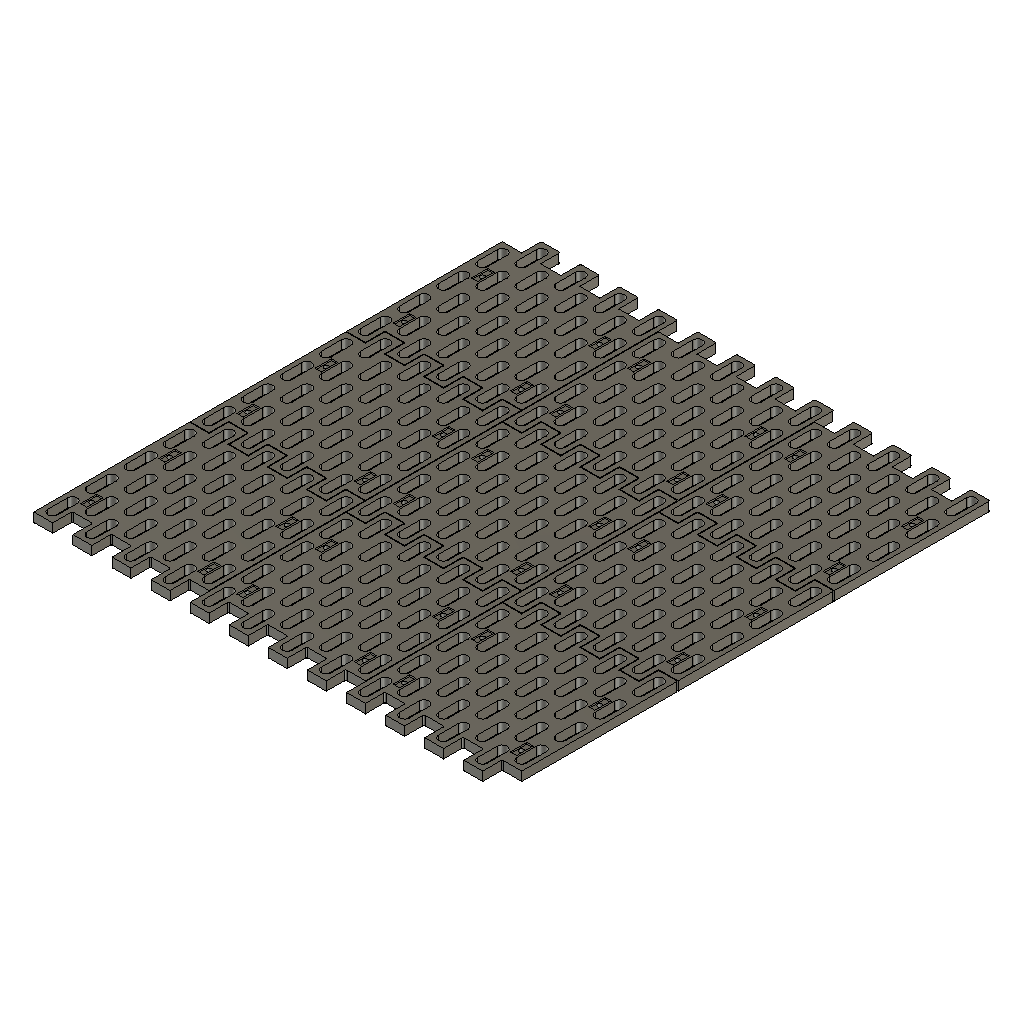
seam-array-3x3-gap-0.35 (Autodesk Fusion 360 design; units mm, degrees)
part number: 2026-10-31-10-06-00-765
part number: 2026-10-31-10-06-01-089
Autodesk Fusion 360 part; units mm, degrees
sketch "01 Main panel web sketch" plane through (0, 0, 0) normal (0, 0, 1) x (1, 0, 0) in component "Panel 80 mm whole-slot coupon"
  line L0 (0.175, 0.175) -> (79.825, 0.175)
  line L1 (79.825, 0.175) -> (79.825, 79.825)
  line L2 (79.825, 79.825) -> (0.175, 79.825)
  line L3 (0.175, 79.825) -> (0.175, 0.175)
  dimension "d71" = 0.175
  dimension "d72" = 0.175
  dimension "d73" = 79.65
  dimension "d74" = 79.65
  constraint horizontal L0
  constraint vertical L1
  constraint horizontal L2
  constraint vertical L3
  measures "d71" horizontal distance of origin L0.start
  measures "d72" vertical distance of origin L0.start
  measures "d73" horizontal distance of L0.start L0.end
  measures "d74" vertical distance of L0.end L1.end
extrude "01 Main panel web" add sketch "01 Main panel web sketch" along normal blind 5 in component "Panel 80 mm whole-slot coupon"
sketch "02 Whole-slot upper tooth sketch" plane through (0, 0, 0) normal (0, 0, 1) x (1, 0, 0) in component "Panel 80 mm whole-slot coupon"
  line L0 (10.175, 79) -> (19.825, 79)
  line L1 (19.825, 79) -> (19.825, 89.825)
  line L2 (19.825, 89.825) -> (10.175, 89.825)
  line L3 (10.175, 89.825) -> (10.175, 79)
  dimension "d77" = 10.175
  dimension "d78" = 79
  dimension "d79" = 9.65
  dimension "d80" = 10.825
  constraint horizontal L0
  constraint vertical L1
  constraint horizontal L2
  constraint vertical L3
  measures "d77" horizontal distance of origin L0.start
  measures "d78" vertical distance of origin L0.start
  measures "d79" horizontal distance of L0.start L0.end
  measures "d80" vertical distance of L0.end L1.end
extrude "02 Whole-slot upper tooth" add sketch "02 Whole-slot upper tooth sketch" along normal blind 5 in component "Panel 80 mm whole-slot coupon"
fillet "02 Rounded tooth tip seed" radius 0.6 2 edges at (19.825, 89.825, 2.5) (10.175, 89.825, 2.5) in component "Panel 80 mm whole-slot coupon"
pattern_linear "03 Upper teeth and rounding follow column count" count 4 spacing 20 along (1, 0, 0) of "02 Whole-slot upper tooth", "02 Rounded tooth tip seed" in component "Panel 80 mm whole-slot coupon"
sketch "04 Lower receiving step sketch" plane through (0, 0, 0) normal (0, 0, 1) x (1, 0, 0) in component "Panel 80 mm whole-slot coupon"
  line L0 (9.825, -1) -> (20.175, -1)
  line L1 (20.175, -1) -> (20.175, 10.175)
  line L2 (20.175, 10.175) -> (9.825, 10.175)
  line L3 (9.825, 10.175) -> (9.825, -1)
  dimension "d89" = 9.825
  dimension "d90" = 1
  dimension "d91" = 10.35
  dimension "d92" = 11.175
  constraint horizontal L0
  constraint vertical L1
  constraint horizontal L2
  constraint vertical L3
  measures "d89" horizontal distance of origin L0.start
  measures "d90" vertical distance of origin L0.start
  measures "d91" horizontal distance of L0.start L0.end
  measures "d92" vertical distance of L0.end L1.end
extrude "04 Lower receiving step" cut sketch "04 Lower receiving step sketch" along normal blind 5 in component "Panel 80 mm whole-slot coupon"
fillet "04 Rounded receiving step seed" radius 0.6 2 edges at (20.175, 10.175, 2.5) (9.825, 10.175, 2.5) in component "Panel 80 mm whole-slot coupon"
pattern_linear "05 Receiving steps and rounding follow column count" count 3 spacing 20 along (1, 0, 0) of "04 Lower receiving step", "04 Rounded receiving step seed" in component "Panel 80 mm whole-slot coupon"
sketch "05 Terminal receiving step sketch" plane through (0, 0, 0) normal (0, 0, 1) x (1, 0, 0) in component "Panel 80 mm whole-slot coupon"
  line L0 (69.825, -1) -> (80.175, -1)
  line L1 (80.175, -1) -> (80.175, 10.175)
  line L2 (80.175, 10.175) -> (69.825, 10.175)
  line L3 (69.825, 10.175) -> (69.825, -1)
  dimension "d101" = 69.825
  dimension "d102" = 1
  dimension "d103" = 10.35
  dimension "d104" = 11.175
  constraint horizontal L0
  constraint vertical L1
  constraint horizontal L2
  constraint vertical L3
  measures "d101" horizontal distance of origin L0.start
  measures "d102" vertical distance of origin L0.start
  measures "d103" horizontal distance of L0.start L0.end
  measures "d104" vertical distance of L0.end L1.end
extrude "05 Terminal receiving step" cut sketch "05 Terminal receiving step sketch" along normal blind 5 in component "Panel 80 mm whole-slot coupon"
fillet "05 Rounded terminal receiving step" radius 0.6 1 edges at (69.825, 10.175, 2.5) in component "Panel 80 mm whole-slot coupon"
sketch "08 Whole A slots constrained seed" plane through (0, 0, 0) normal (0, 0, 1) x (1, 0, 0) in component "Panel 80 mm whole-slot coupon"
  line L0 (7.5, 5) -> (7.5, 15)
  arc A0 (7.5, 15) -> (2.5, 15) centre (5, 15) ccw
  line L1 (2.5, 15) -> (2.5, 5)
  arc A1 (2.5, 5) -> (7.5, 5) centre (5, 5) ccw
  line L2 (5, 5) -> (5, 15) construction
  line L3 (5, 5) -> (15, 5) construction
  dimension "d109" = 5
  dimension "d110" = 10
  dimension "d111" = 90
  dimension "d112" = 10
  dimension "d113" = 5
  dimension "d114" = 5
  constraint tangent L0 A0
  constraint tangent A0 L1
  constraint tangent L1 A1
  constraint tangent L0 A1
  constraint parallel L0 L1
  constraint horizontal L3
  measures "d109" diameter of A0
  measures "d110" distance of A1.centre A0.centre
  measures "d111" angle of L2 L3
  measures "d112" horizontal distance of A1.centre L3.end
  measures "d113" horizontal distance of origin A1.centre
  measures "d114" vertical distance of origin A1.centre
extrude "08 Whole A slots through cut" cut sketch "08 Whole A slots constrained seed" along normal blind 5 in component "Panel 80 mm whole-slot coupon"
pattern_linear "08 Whole A slots lattice" count 4 spacing 20 along (1, 0, 0) count 4 spacing 20 along (0, 1, 0) of "08 Whole A slots through cut" in component "Panel 80 mm whole-slot coupon"
sketch "09 Whole B slots owned by this panel constrained seed" plane through (0, 0, 0) normal (0, 0, 1) x (1, 0, 0) in component "Panel 80 mm whole-slot coupon"
  line L0 (17.5, 15) -> (17.5, 25)
  arc A0 (17.5, 25) -> (12.5, 25) centre (15, 25) ccw
  line L1 (12.5, 25) -> (12.5, 15)
  arc A1 (12.5, 15) -> (17.5, 15) centre (15, 15) ccw
  line L2 (15, 15) -> (15, 25) construction
  line L3 (15, 15) -> (25, 15) construction
  dimension "d121" = 5
  dimension "d122" = 10
  dimension "d123" = 90
  dimension "d124" = 10
  dimension "d125" = 15
  dimension "d126" = 15
  constraint tangent L0 A0
  constraint tangent A0 L1
  constraint tangent L1 A1
  constraint tangent L0 A1
  constraint parallel L0 L1
  constraint horizontal L3
  measures "d121" diameter of A0
  measures "d122" distance of A1.centre A0.centre
  measures "d123" angle of L2 L3
  measures "d124" horizontal distance of A1.centre L3.end
  measures "d125" horizontal distance of origin A1.centre
  measures "d126" vertical distance of origin A1.centre
extrude "09 Whole B slots owned by this panel through cut" cut sketch "09 Whole B slots owned by this panel constrained seed" along normal blind 5 in component "Panel 80 mm whole-slot coupon"
pattern_linear "09 Whole B slots owned by this panel lattice" count 4 spacing 20 along (1, 0, 0) count 4 spacing 20 along (0, 1, 0) of "09 Whole B slots owned by this panel through cut" in component "Panel 80 mm whole-slot coupon"
fillet "10 Rounded slot entrances and face outline" radius 0.4 2 faces at (10.6109, 18.9001, 0) (10.6109, 18.9001, 0) in component "Panel 80 mm whole-slot coupon"
sketch "11 M2 through bore sketch" plane through (0, 0, 0) normal (0, 0, 1) x (1, 0, 0) in component "Panel 80 mm whole-slot coupon"
  circle A0 centre (10, 20) radius 1.2
  dimension "d135" = 10
  dimension "d136" = 20
  dimension "d137" = 2.4
  measures "d135" horizontal distance of origin A0.centre
  measures "d136" vertical distance of origin A0.centre
  measures "d137" diameter of A0
extrude "11 M2 through bore" cut sketch "11 M2 through bore sketch" along normal blind 5 in component "Panel 80 mm whole-slot coupon"
sketch "12 Flush countersink sketch" plane through (0, 0, 0) normal (0, 0, 1) x (1, 0, 0) in component "Panel 80 mm whole-slot coupon"
  circle A0 centre (10, 20) radius 2
  dimension "d140" = 10
  dimension "d141" = 20
  dimension "d142" = 4
  measures "d140" horizontal distance of origin A0.centre
  measures "d141" vertical distance of origin A0.centre
  measures "d142" diameter of A0
extrude "12 Flush countersink" cut sketch "12 Flush countersink sketch" along normal blind 0.8 draft -45 in component "Panel 80 mm whole-slot coupon"
ref_plane "WorkPlane1" through (0, 0, 5) normal (0, 0, 1) x (1, 0, 0) in component "Panel 80 mm whole-slot coupon"
sketch "13 Blind rear registration sketch" plane through (0, 0, 5) normal (0, 0, 1) x (1, 0, 0) in component "Panel 80 mm whole-slot coupon"
  line L0 (8.4, 15.8) -> (11.6, 15.8)
  line L1 (11.6, 15.8) -> (11.6, 24.2)
  line L2 (11.6, 24.2) -> (8.4, 24.2)
  line L3 (8.4, 24.2) -> (8.4, 15.8)
  dimension "d147" = 8.4
  dimension "d148" = 15.8
  dimension "d149" = 3.2
  dimension "d150" = 8.4
  constraint horizontal L0
  constraint vertical L1
  constraint horizontal L2
  constraint vertical L3
  measures "d147" horizontal distance of origin L0.start
  measures "d148" vertical distance of origin L0.start
  measures "d149" horizontal distance of L0.start L0.end
  measures "d150" vertical distance of L0.end L1.end
extrude "13 Blind rear registration" cut sketch "13 Blind rear registration sketch" against normal blind 0.8 in component "Panel 80 mm whole-slot coupon"
sketch "11 M2 through bore sketch (1)" plane through (0, 0, 0) normal (0, 0, 1) x (1, 0, 0) in component "Panel 80 mm whole-slot coupon"
  circle A0 centre (10, 60) radius 1.2
  dimension "d153" = 10
  dimension "d154" = 60
  dimension "d155" = 2.4
  measures "d153" horizontal distance of origin A0.centre
  measures "d154" vertical distance of origin A0.centre
  measures "d155" diameter of A0
extrude "11 M2 through bore (1)" cut sketch "11 M2 through bore sketch (1)" along normal blind 5 in component "Panel 80 mm whole-slot coupon"
sketch "12 Flush countersink sketch (1)" plane through (0, 0, 0) normal (0, 0, 1) x (1, 0, 0) in component "Panel 80 mm whole-slot coupon"
  circle A0 centre (10, 60) radius 2
  dimension "d158" = 10
  dimension "d159" = 60
  dimension "d160" = 4
  measures "d158" horizontal distance of origin A0.centre
  measures "d159" vertical distance of origin A0.centre
  measures "d160" diameter of A0
extrude "12 Flush countersink (1)" cut sketch "12 Flush countersink sketch (1)" along normal blind 0.8 draft -45 in component "Panel 80 mm whole-slot coupon"
ref_plane "WorkPlane2" through (0, 0, 5) normal (0, 0, 1) x (1, 0, 0) in component "Panel 80 mm whole-slot coupon"
sketch "13 Blind rear registration sketch (1)" plane through (0, 0, 5) normal (0, 0, 1) x (1, 0, 0) in component "Panel 80 mm whole-slot coupon"
  line L0 (8.4, 55.8) -> (11.6, 55.8)
  line L1 (11.6, 55.8) -> (11.6, 64.2)
  line L2 (11.6, 64.2) -> (8.4, 64.2)
  line L3 (8.4, 64.2) -> (8.4, 55.8)
  dimension "d165" = 8.4
  dimension "d166" = 55.8
  dimension "d167" = 3.2
  dimension "d168" = 8.4
  constraint horizontal L0
  constraint vertical L1
  constraint horizontal L2
  constraint vertical L3
  measures "d165" horizontal distance of origin L0.start
  measures "d166" vertical distance of origin L0.start
  measures "d167" horizontal distance of L0.start L0.end
  measures "d168" vertical distance of L0.end L1.end
extrude "13 Blind rear registration (1)" cut sketch "13 Blind rear registration sketch (1)" against normal blind 0.8 in component "Panel 80 mm whole-slot coupon"
sketch "11 M2 through bore sketch (2)" plane through (0, 0, 0) normal (0, 0, 1) x (1, 0, 0) in component "Panel 80 mm whole-slot coupon"
  circle A0 centre (70, 20) radius 1.2
  dimension "d171" = 70
  dimension "d172" = 20
  dimension "d173" = 2.4
  measures "d171" horizontal distance of origin A0.centre
  measures "d172" vertical distance of origin A0.centre
  measures "d173" diameter of A0
extrude "11 M2 through bore (2)" cut sketch "11 M2 through bore sketch (2)" along normal blind 5 in component "Panel 80 mm whole-slot coupon"
sketch "12 Flush countersink sketch (2)" plane through (0, 0, 0) normal (0, 0, 1) x (1, 0, 0) in component "Panel 80 mm whole-slot coupon"
  circle A0 centre (70, 20) radius 2
  dimension "d176" = 70
  dimension "d177" = 20
  dimension "d178" = 4
  measures "d176" horizontal distance of origin A0.centre
  measures "d177" vertical distance of origin A0.centre
  measures "d178" diameter of A0
extrude "12 Flush countersink (2)" cut sketch "12 Flush countersink sketch (2)" along normal blind 0.8 draft -45 in component "Panel 80 mm whole-slot coupon"
ref_plane "WorkPlane3" through (0, 0, 5) normal (0, 0, 1) x (1, 0, 0) in component "Panel 80 mm whole-slot coupon"
sketch "13 Blind rear registration sketch (2)" plane through (0, 0, 5) normal (0, 0, 1) x (1, 0, 0) in component "Panel 80 mm whole-slot coupon"
  line L0 (68.4, 15.8) -> (71.6, 15.8)
  line L1 (71.6, 15.8) -> (71.6, 24.2)
  line L2 (71.6, 24.2) -> (68.4, 24.2)
  line L3 (68.4, 24.2) -> (68.4, 15.8)
  dimension "d183" = 68.4
  dimension "d184" = 15.8
  dimension "d185" = 3.2
  dimension "d186" = 8.4
  constraint horizontal L0
  constraint vertical L1
  constraint horizontal L2
  constraint vertical L3
  measures "d183" horizontal distance of origin L0.start
  measures "d184" vertical distance of origin L0.start
  measures "d185" horizontal distance of L0.start L0.end
  measures "d186" vertical distance of L0.end L1.end
extrude "13 Blind rear registration (2)" cut sketch "13 Blind rear registration sketch (2)" against normal blind 0.8 in component "Panel 80 mm whole-slot coupon"
sketch "11 M2 through bore sketch (3)" plane through (0, 0, 0) normal (0, 0, 1) x (1, 0, 0) in component "Panel 80 mm whole-slot coupon"
  circle A0 centre (70, 60) radius 1.2
  dimension "d189" = 70
  dimension "d190" = 60
  dimension "d191" = 2.4
  measures "d189" horizontal distance of origin A0.centre
  measures "d190" vertical distance of origin A0.centre
  measures "d191" diameter of A0
extrude "11 M2 through bore (3)" cut sketch "11 M2 through bore sketch (3)" along normal blind 5 in component "Panel 80 mm whole-slot coupon"
sketch "12 Flush countersink sketch (3)" plane through (0, 0, 0) normal (0, 0, 1) x (1, 0, 0) in component "Panel 80 mm whole-slot coupon"
  circle A0 centre (70, 60) radius 2
  dimension "d194" = 70
  dimension "d195" = 60
  dimension "d196" = 4
  measures "d194" horizontal distance of origin A0.centre
  measures "d195" vertical distance of origin A0.centre
  measures "d196" diameter of A0
extrude "12 Flush countersink (3)" cut sketch "12 Flush countersink sketch (3)" along normal blind 0.8 draft -45 in component "Panel 80 mm whole-slot coupon"
ref_plane "WorkPlane4" through (0, 0, 5) normal (0, 0, 1) x (1, 0, 0) in component "Panel 80 mm whole-slot coupon"
sketch "13 Blind rear registration sketch (3)" plane through (0, 0, 5) normal (0, 0, 1) x (1, 0, 0) in component "Panel 80 mm whole-slot coupon"
  line L0 (68.4, 55.8) -> (71.6, 55.8)
  line L1 (71.6, 55.8) -> (71.6, 64.2)
  line L2 (71.6, 64.2) -> (68.4, 64.2)
  line L3 (68.4, 64.2) -> (68.4, 55.8)
  dimension "d201" = 68.4
  dimension "d202" = 55.8
  dimension "d203" = 3.2
  dimension "d204" = 8.4
  constraint horizontal L0
  constraint vertical L1
  constraint horizontal L2
  constraint vertical L3
  measures "d201" horizontal distance of origin L0.start
  measures "d202" vertical distance of origin L0.start
  measures "d203" horizontal distance of L0.start L0.end
  measures "d204" vertical distance of L0.end L1.end
extrude "13 Blind rear registration (3)" cut sketch "13 Blind rear registration sketch (3)" against normal blind 0.8 in component "Panel 80 mm whole-slot coupon"
pattern_linear "Nine coupons surround center panel for service test" [suppressed]
component "Panel 80 mm whole-slot coupon" placed x (1, 0, 0) y (0, 1, 0) z (0, 0, 1) at (0, 0, 0)
component "Panel 80 mm whole-slot coupon" placed x (1, 0, 0) y (0, 1, 0) z (0, 0, 1) at (80, 0, 0)
component "Panel 80 mm whole-slot coupon" placed x (1, 0, 0) y (0, 1, 0) z (0, 0, 1) at (160, 0, 0)
component "Panel 80 mm whole-slot coupon" placed x (1, 0, 0) y (0, 1, 0) z (0, 0, 1) at (0, 80, 0)
component "Panel 80 mm whole-slot coupon" placed x (1, 0, 0) y (0, 1, 0) z (0, 0, 1) at (80, 80, 0)
component "Panel 80 mm whole-slot coupon" placed x (1, 0, 0) y (0, 1, 0) z (0, 0, 1) at (160, 80, 0)
component "Panel 80 mm whole-slot coupon" placed x (1, 0, 0) y (0, 1, 0) z (0, 0, 1) at (0, 160, 0)
component "Panel 80 mm whole-slot coupon" placed x (1, 0, 0) y (0, 1, 0) z (0, 0, 1) at (80, 160, 0)
component "Panel 80 mm whole-slot coupon" placed x (1, 0, 0) y (0, 1, 0) z (0, 0, 1) at (160, 160, 0)
equation "columns = 4" comment "Even integer 4..14; each cell is 20 mm"
equation "rows = 4" comment "Even integer 4..14"
equation "pitch = 20 mm" comment "Keep for dense SKADIS compatible lattice"
equation "panelWidth = columns * pitch" comment "Nominal module pitch X"
equation "panelHeight = rows * pitch" comment "Nominal module pitch Y"
equation "seamGap = 0.35 mm" comment "Physical envelope shrinks around fixed lattice"
equation "boardThickness = 5 mm" comment "Fit-test with real hooks"
equation "slotWidth = 5 mm" comment "Minimum throat width"
equation "slotHeight = 15 mm" comment "Minimum throat height"
equation "entryRadius = 0.4 mm" comment "Front slot and perimeter edge rounding"
equation "cornerRadius = 6 mm" comment "Plan-view panel corner rounding"
equation "hookClearance = 10 mm" comment "PROVISIONAL unobstructed depth behind board; carriers begin at its rear boundary"
equation "frameZ = carrierZ + carrierThickness" comment "Front extrusion datum"
equation "profileMouth = 6.28 mm" comment "User measured mouth"
equation "profileCavity = 11 mm" comment "User measured widest cavity"
equation "profileDepth = 6.2 mm" comment "User measured face-to-floor depth"
equation "profileFloor = 5.7 mm" comment "User estimate, lower confidence"
equation "profileLip = 1.5 mm" comment "Unmeasured; tentative comparable catalog value"
equation "profileTaperStart = profileDepth - ( profileCavity - profileFloor ) / 2" comment "Assumed 45-degree inner slopes"
equation "profileBore = 5 mm" comment "Unmeasured central bore, reference only"
equation "nutWidth = 8.8 mm" comment "Provisional low-profile METAL T-nut envelope, not old rectangular carrier"
equation "nutLength = 12 mm" comment "End-loaded anti-rotation metal nut envelope"
equation "nutThickness = 2.7 mm" comment "Thin nut reference; fit/load still unverified"
equation "jointLeg = 18 mm" comment "In-bay angle footprint"
equation "jointThickness = 3 mm" comment "Metal bracket thickness"
equation "jointDepth = 16 mm" comment "Bracket depth within 20 mm rail"
equation "sideScrewLength = 8 mm" comment "M5x8 reference; check against actual bracket and nut"
equation "wallTabHeight = 24 mm" comment "Tab along extrusion"
equation "wallTabReach = 22 mm" comment "Tab into open bay"
equation "wallAnchorClearance = 6.5 mm" comment "Placeholder wall anchor interface"
equation "wallDriverDiameter = 12 mm" comment "Clear tool envelope in open bays"
equation "keyDriverDiameter = 5 mm" comment "Short hex-key working-leg envelope"
equation "keyDriverReach = 20 mm" comment "Short hex-key working-leg reach"
equation "supportWidth = 3.2 mm" comment "Prototype blade; two perimeter lines need print review"
equation "supportLength = 12 mm" comment "Compression bearing length"
equation "hookEnvelopeWidth = 6 mm" comment "Conservative provisional continuous hook column"
equation "carrierThickness = 7 mm" comment "Room for captive M2 nut and stock M5x12"
equation "panelClearance = 2.4 mm" comment "M2 clearance"
equation "panelHeadPocket = 4 mm" comment "DIN965 3.8 mm head plus 0.1 mm recess"
equation "carrierHeadPocket = 9.4 mm" comment "DIN965 M5 9.2 mm head plus recess"
equation "carrierBore = 5.5 mm" comment "M5 clearance"
equation "tongueWidth = 2.8 mm" comment "Rear axial registration tongue"
equation "tongueLength = 8 mm" comment "Axial release registration"
equation "tongueDepth = 0.6 mm" comment "Tongue engagement"
equation "registerClearance = 0.2 mm" comment "Each side of printed tongue"
equation "carrierZ = boardThickness + hookClearance" comment "Rear hook cavity boundary"
equation "stepCorner = 0.6 mm" comment "Small plan corner relief; printed fit remains untested"
equation "couponLeft = 0" comment "Edge topology selected when generated; regenerate to change edge type"
equation "couponRight = 0" comment "Edge topology selected when generated; regenerate to change edge type"
equation "couponBottom = 0" comment "Edge topology selected when generated; regenerate to change edge type"
equation "couponTop = 0" comment "Edge topology selected when generated; regenerate to change edge type"
equation "d71 = abs(( 0 mm ) + seamGap / 2)"
equation "d72 = abs(( 0 mm ) + seamGap / 2)"
equation "d73 = panelWidth - seamGap"
equation "d74 = panelHeight - seamGap"
equation "d75 = boardThickness"
equation "d77 = abs(( 0 mm ) + pitch / 2 + seamGap / 2)"
equation "d78 = abs(( 0 mm ) + panelHeight - 1 mm)"
equation "d79 = pitch / 2 - seamGap"
equation "d80 = pitch / 2 + 1 mm - seamGap / 2"
equation "d81 = boardThickness"
equation "d84 = stepCorner"
equation "d85 = columns"
equation "d87 = pitch"
equation "d88 = pitch"
equation "d89 = abs(( 0 mm ) + pitch / 2 - seamGap / 2)"
equation "d90 = abs(( 0 mm ) - 1 mm)"
equation "d91 = pitch / 2 + seamGap"
equation "d92 = pitch / 2 + 1 mm + seamGap / 2"
equation "d93 = boardThickness"
equation "d96 = stepCorner"
equation "d97 = columns - 1"
equation "d99 = pitch"
equation "d100 = pitch"
equation "d101 = abs(( 0 mm ) + panelWidth - pitch / 2 - seamGap / 2)"
equation "d102 = abs(( 0 mm ) - 1 mm)"
equation "d103 = pitch / 2 + seamGap"
equation "d104 = pitch / 2 + 1 mm + seamGap / 2"
equation "d105 = boardThickness"
equation "d108 = stepCorner"
equation "d109 = slotWidth"
equation "d110 = slotHeight - slotWidth"
equation "d112 = pitch / 2"
equation "d113 = abs(( 0 mm ) + pitch / 4)"
equation "d114 = abs(( ( 0 mm ) + pitch / 2 ) - ( slotHeight - slotWidth ) / 2)"
equation "d115 = boardThickness"
equation "d117 = columns"
equation "d118 = rows"
equation "d119 = pitch"
equation "d120 = pitch"
equation "d121 = slotWidth"
equation "d122 = slotHeight - slotWidth"
equation "d124 = pitch / 2"
equation "d125 = abs(( 0 mm ) + 3 * pitch / 4)"
equation "d126 = abs(( ( 0 mm ) + pitch ) - ( slotHeight - slotWidth ) / 2)"
equation "d127 = boardThickness"
equation "d129 = columns"
equation "d130 = rows - couponTop"
equation "d131 = pitch"
equation "d132 = pitch"
equation "d134 = entryRadius"
equation "d135 = abs(( 0 mm ) + pitch / 2)"
equation "d136 = abs(( 0 mm ) + pitch)"
equation "d137 = panelClearance"
equation "d138 = boardThickness"
equation "d140 = abs(( 0 mm ) + pitch / 2)"
equation "d141 = abs(( 0 mm ) + pitch)"
equation "d142 = panelHeadPocket"
equation "d143 = ( panelHeadPocket - panelClearance ) / 2"
equation "d145 = boardThickness"
equation "d147 = abs(( 0 mm ) + pitch / 2 - tongueWidth / 2 - registerClearance)"
equation "d148 = abs(( 0 mm ) + pitch - tongueLength / 2 - registerClearance)"
equation "d149 = tongueWidth + 2 * registerClearance"
equation "d150 = tongueLength + 2 * registerClearance"
equation "d151 = -tongueDepth - 0.2 mm"
equation "d153 = abs(( 0 mm ) + pitch / 2)"
equation "d154 = abs(( 0 mm ) + panelHeight - pitch)"
equation "d155 = panelClearance"
equation "d156 = boardThickness"
equation "d158 = abs(( 0 mm ) + pitch / 2)"
equation "d159 = abs(( 0 mm ) + panelHeight - pitch)"
equation "d160 = panelHeadPocket"
equation "d161 = ( panelHeadPocket - panelClearance ) / 2"
equation "d163 = boardThickness"
equation "d165 = abs(( 0 mm ) + pitch / 2 - tongueWidth / 2 - registerClearance)"
equation "d166 = abs(( 0 mm ) + panelHeight - pitch - tongueLength / 2 - registerClearance)"
equation "d167 = tongueWidth + 2 * registerClearance"
equation "d168 = tongueLength + 2 * registerClearance"
equation "d169 = -tongueDepth - 0.2 mm"
equation "d171 = abs(( 0 mm ) + panelWidth - pitch / 2)"
equation "d172 = abs(( 0 mm ) + pitch)"
equation "d173 = panelClearance"
equation "d174 = boardThickness"
equation "d176 = abs(( 0 mm ) + panelWidth - pitch / 2)"
equation "d177 = abs(( 0 mm ) + pitch)"
equation "d178 = panelHeadPocket"
equation "d179 = ( panelHeadPocket - panelClearance ) / 2"
equation "d181 = boardThickness"
equation "d183 = abs(( 0 mm ) + panelWidth - pitch / 2 - tongueWidth / 2 - registerClearance)"
equation "d184 = abs(( 0 mm ) + pitch - tongueLength / 2 - registerClearance)"
equation "d185 = tongueWidth + 2 * registerClearance"
equation "d186 = tongueLength + 2 * registerClearance"
equation "d187 = -tongueDepth - 0.2 mm"
equation "d189 = abs(( 0 mm ) + panelWidth - pitch / 2)"
equation "d190 = abs(( 0 mm ) + panelHeight - pitch)"
equation "d191 = panelClearance"
equation "d192 = boardThickness"
equation "d194 = abs(( 0 mm ) + panelWidth - pitch / 2)"
equation "d195 = abs(( 0 mm ) + panelHeight - pitch)"
equation "d196 = panelHeadPocket"
equation "d197 = ( panelHeadPocket - panelClearance ) / 2"
equation "d199 = boardThickness"
equation "d201 = abs(( 0 mm ) + panelWidth - pitch / 2 - tongueWidth / 2 - registerClearance)"
equation "d202 = abs(( 0 mm ) + panelHeight - pitch - tongueLength / 2 - registerClearance)"
equation "d203 = tongueWidth + 2 * registerClearance"
equation "d204 = tongueLength + 2 * registerClearance"
equation "d205 = -tongueDepth - 0.2 mm"
equation "d209 = panelWidth"
equation "d210 = panelHeight"
